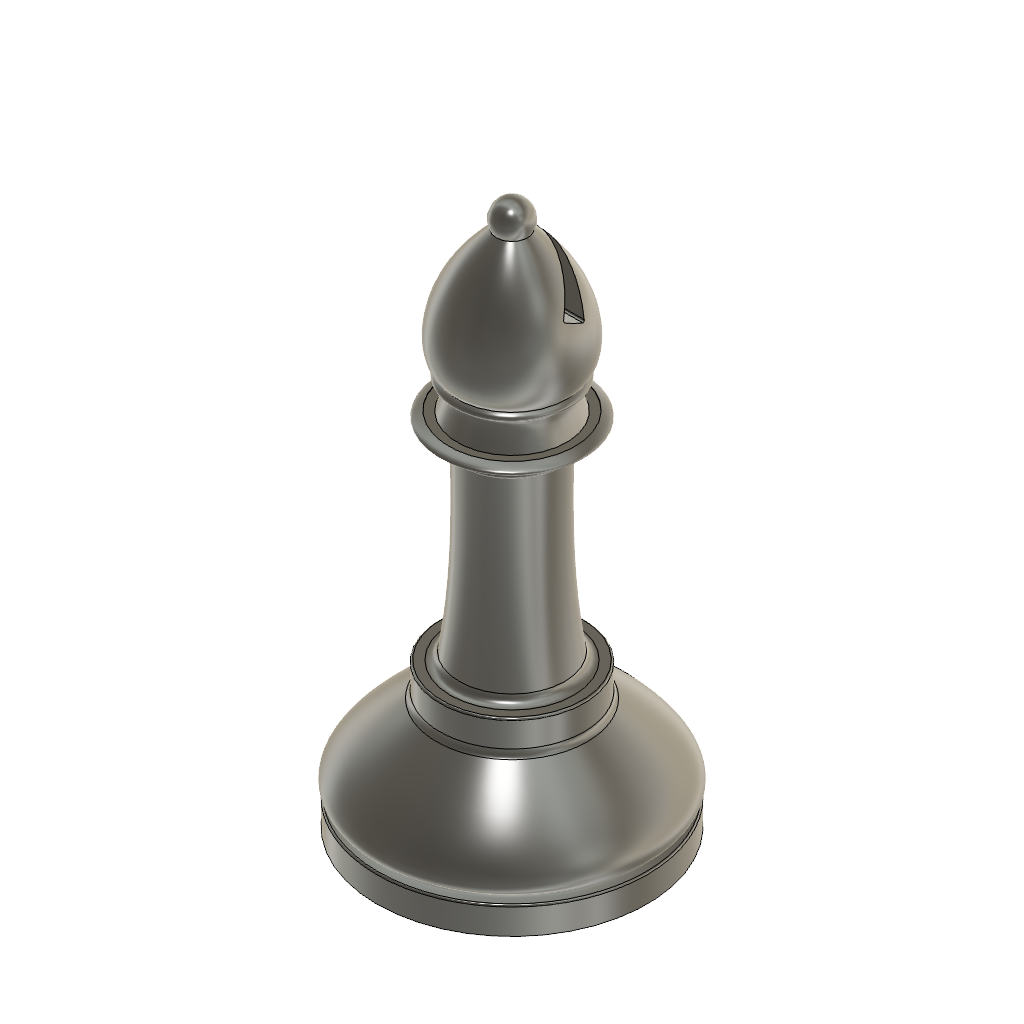
Bishop (Autodesk Fusion 360 design; units mm, degrees)
Autodesk Fusion 360 part; units mm, degrees
sketch "Sketch1" plane through (0, 0, 0) normal (1, 0, 0) x (0, 1, 0)
  line L0 (0, 0) -> (0, 76.708)
  circle A0 centre (-0.0002, 74.168) radius 2.54
  line L1 (0, 0) -> (19.05, 0)
  line L2 (19.05, 0) -> (19.05, 3.81)
  spline S0 degree 5 poles (19.05, 3.81) (18.8535, 3.8497) (18.4978, 3.9262) (18.0755, 4.0326) (17.7369, 4.1573) (17.6769, 4.291) (17.9327, 4.4218) (18.3882, 4.5917) (18.8859, 4.8557) (19.2646, 5.2684) (19.3995, 5.8693) (19.2151, 6.6787) (18.6677, 7.7047) (17.7385, 8.947) (16.4244, 10.4003) (14.7318, 12.0571) (13.0827, 13.5397) (11.6839, 14.7377) (10.6799, 15.5742) (10.16, 16.002) knots 0 0 0 0 0 0 0.066667 0.133333 0.2 0.266667 0.333333 0.4 0.466667 0.533333 0.6 0.666667 0.733333 0.8 0.866667 0.933333 1 1 1 1 1 1
  line L3 (10.16, 16.002) -> (10.16, 20.32)
  line L4 (10.16, 20.32) -> (7.62, 20.32)
  spline S1 degree 5 poles (7.62, 20.32) (7.5394, 20.7696) (7.3832, 21.6811) (7.164, 23.0853) (6.9027, 25.0327) (6.6306, 27.6003) (6.4173, 30.3109) (6.2661, 33.1729) (6.1765, 36.1851) (6.1439, 39.3363) (6.1631, 42.6137) (6.216, 45.3271) (6.2753, 47.4102) (6.3235, 48.8199) (6.3498, 49.53) knots 0 0 0 0 0 0 0.1 0.2 0.3 0.4 0.5 0.6 0.7 0.8 0.9 1 1 1 1 1 1
  line L5 (6.3498, 49.53) -> (8.8898, 49.53)
  spline S2 degree 5 poles (8.8898, 49.53) (8.9864, 49.5463) (9.1714, 49.5796) (9.4232, 49.632) (9.7073, 49.7068) (9.9703, 49.809) (10.1331, 49.9206) (10.1878, 50.0425) (10.1304, 50.1749) (9.966, 50.3174) (9.7028, 50.4693) (9.4198, 50.5976) (9.1693, 50.6974) (8.9857, 50.7655) (8.8898, 50.8) knots 0 0 0 0 0 0 0.1 0.2 0.3 0.4 0.5 0.6 0.7 0.8 0.9 1 1 1 1 1 1
  line L6 (8.8898, 50.8) -> (8.8898, 50.6966)
  line L7 (8.8898, 50.6966) -> (7.7101, 50.6966)
  spline S3 degree 5 poles (7.7101, 50.6966) (7.657, 50.8474) (7.5549, 51.1411) (7.4135, 51.5582) (7.2485, 52.0671) (7.0822, 52.6238) (6.9568, 53.1005) (6.8736, 53.4977) (6.8337, 53.8179) (6.8384, 54.0662) (6.8883, 54.2516) (6.9839, 54.388) (7.1235, 54.4926) (7.3017, 54.5829) (7.5077, 54.6738) (7.7226, 54.7749) (7.9217, 54.8905) (8.0791, 55.0218) (8.1707, 55.1676) (8.1794, 55.3268) (8.0962, 55.4984) (7.9534, 55.6453) (7.8033, 55.7606) (7.6841, 55.8398) (7.6198, 55.88) knots 0 0 0 0 0 0 0.05 0.1 0.15 0.2 0.25 0.3 0.35 0.4 0.45 0.5 0.55 0.6 0.65 0.7 0.75 0.8 0.85 0.9 0.95 1 1 1 1 1 1
  spline S4 degree 5 poles (2.216, 72.9271) (2.4871, 72.671) (3.0169, 72.157) (3.7739, 71.3804) (4.7074, 70.3336) (5.7445, 69.0065) (6.6465, 67.6627) (7.4075, 66.3067) (8.0227, 64.9469) (8.4894, 63.5967) (8.8099, 62.2764) (8.9913, 61.0119) (9.0423, 59.8306) (8.9728, 58.7585) (8.7916, 57.8167) (8.5063, 57.0161) (8.1992, 56.4906) (7.926, 56.1606) (7.725, 55.9688) (7.6198, 55.88) knots 0 0 0 0 0 0 0.066667 0.133333 0.2 0.266667 0.333333 0.4 0.466667 0.533333 0.6 0.666667 0.733333 0.8 0.866667 0.933333 1 1 1 1 1 1
  spline S5 degree 5 poles (6.0958, 48.514) (6.1921, 48.4835) (6.3763, 48.4226) (6.6274, 48.3311) (6.911, 48.2092) (7.1741, 48.0568) (7.3377, 47.9044) (7.3937, 47.752) (7.3377, 47.5996) (7.1741, 47.4472) (6.911, 47.2948) (6.6274, 47.1729) (6.3763, 47.0814) (6.1921, 47.0205) (6.0958, 46.99) knots 0 0 0 0 0 0 0.1 0.2 0.3 0.4 0.5 0.6 0.7 0.8 0.9 1 1 1 1 1 1
  point P0 (17.78, 4.318)
  point P1 (19.05, 5.08)
  point P2 (6.35, 31.75)
  point P3 (10.1598, 50.038)
  point P4 (6.8578, 54.102)
  point P5 (7.3658, 54.61)
  point P6 (8.1278, 55.118)
  point P7 (8.1856, 64.4216)
  point P8 (8.8898, 58.42)
  point P9 (7.3658, 47.752)
  dimension "d2" = 5.08
  dimension "d3" = 19.05
  constraint coincident L0.start L1.start
  constraint vertical L0
  constraint coincident L0.end A0
  constraint perpendicular L0 L1
  constraint perpendicular L1 L2
  constraint parallel L0 L3
  constraint perpendicular L3 L4
  constraint horizontal L5
  constraint vertical L6
  constraint perpendicular L6 L7
  constraint coincident A0 S4.start
  measures "d2" diameter of A0
  measures "d3" distance of L0.start L1.end
revolve "Revolve1" add sketch "Sketch1" angle 360 about axis through (0, 0, 0) along (0, 0, 1) contours L0 A0 L1 L2 S0 L3 L4 S1 L5 S2 L6 L7 S3 S4 | L0 A0 | S1 S5 picked at (0.7517, 74.7299) in component "Component"
fillet "Fillet1" radius 0.254 1 edges at (-9.4724, 3.674, 20.32) in component "Component"
fillet "Fillet2" radius 1.27 2 edges at (-9.4724, 3.674, 16.002) (-7.1043, 2.7555, 20.32) in component "Component"
fillet "Fillet3" radius 0.254 1 edges at (-17.7608, 6.8888, 3.81) in component "Component"
sketch "Sketch2" plane through (0, 0, 0) normal (1, 0, 0) x (0, 1, 0)
  line L0 (-0.508, 65.532) -> (2.286, 64.262)
  line L1 (2.286, 64.262) -> (4.826, 71.628)
  line L2 (4.064, 72.39) -> (4.826, 71.628)
  line L3 (-0.508, 65.532) -> (4.064, 72.39)
extrude "Extrude1" cut sketch "Sketch2" along normal mid plane 25.4 in component "Component"
fillet "Fillet4" radius 0.254 2 edges at (0, -0.508, 65.532) (0, 2.286, 64.262) in component "Component"
component "Component" placed x (1, 0, 0) y (0, 1, 0) z (0, 0, 1) at (0, 0, 0)
